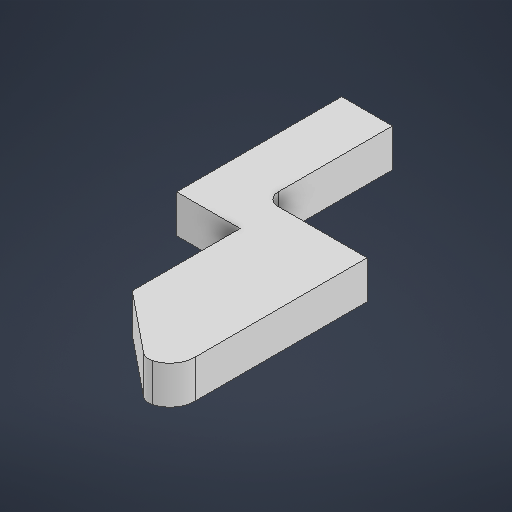
# Autodesk Inventor part: 6_05_piece_mobile
Saved by Autodesk Inventor 2026 (Build 300175000, 175)
## iProperties
Created: 2025-06-18
Part Number: 6_05_piece_mobile
Material: Générique
Document SubType Name: Modeling
Designer: Diogo
Density: 1 g/cm^3
Appearance: Par défaut
Author: Diogo
Autodesk Inventor part; units mm, degrees
ref_plane "YZ Plane" through (0, 0, 0) normal (1, 0, 0) x (0, 1, 0)
ref_plane "XZ Plane" through (0, 0, 0) normal (0, 1, 0) x (-1, 0, 0)
ref_plane "XY Plane" through (0, 0, 0) normal (0, 0, 1) x (1, 0, 0)
sketch "Esquisse1" plane through (0, 0, 0) normal (0, 1, 0) x (-1, 0, 0)
  line L0 (0, 0) -> (0, -26)
  line L1 (0, -26) -> (-8, -26)
  line L2 (-8, -26) -> (-8, -6)
  line L3 (-8, -6) -> (-24, -6)
  line L4 (0, 0) -> (-10, 0)
  line L5 (-24, -6) -> (-24, 21.0891)
  line L6 (-10, 0) -> (-10, 17)
  arc A0 (-21.1804, 24.9109) -> (-24, 21.0891) centre (-20, 21.0891) ccw
  line L7 (-10, 25) -> (-19.5871, 25) construction
  line L8 (-19.5871, 25) -> (-19.5871, 17) construction
  line L9 (-19.5871, 17) -> (-10, 17) construction
  line L10 (-10, 17) -> (-10, 25) construction
  line L11 (-10, 17) -> (-19.3318, 24.5545)
  arc A1 (-19.3318, 24.5545) -> (-21.1804, 24.9109) centre (-20.5902, 23) ccw
  point P0 (-24, 25)
  dimension "d0" = 26
  dimension "d1" = 8
  dimension "d2" = 20
  dimension "d3" = 16
  dimension "d4" = 10
  dimension "d5" = 31
  dimension "d7" = 4
  dimension "d8" = 8
  dimension "d9" = 2
  dimension "d10" = 25
  constraints: 24 end point, 4 perpendicular, 4 point on circle, 3 tangent, 3 vertical, 2 centre point, 2 horizontal, 2 parallel, 1 point on line
  measures "d0" distance of L0.start L0.end
  measures "d1" distance of L0.end L1.end
  measures "d2" distance of L1.end L2.end
  measures "d3" distance of L2.end L3.end
  measures "d4" distance of L0.start L4.end
  measures "d5" distance of L3.end point (-24, 25)
  measures "d7" radius of A0
  measures "d8" distance of L8.end L7.end
  measures "d9" radius of A1
extrude "Extrusion1" add sketch "Esquisse1" along normal blind 6
fillet "Congé1" radius 2 1 edges at (8, 3, -6)
